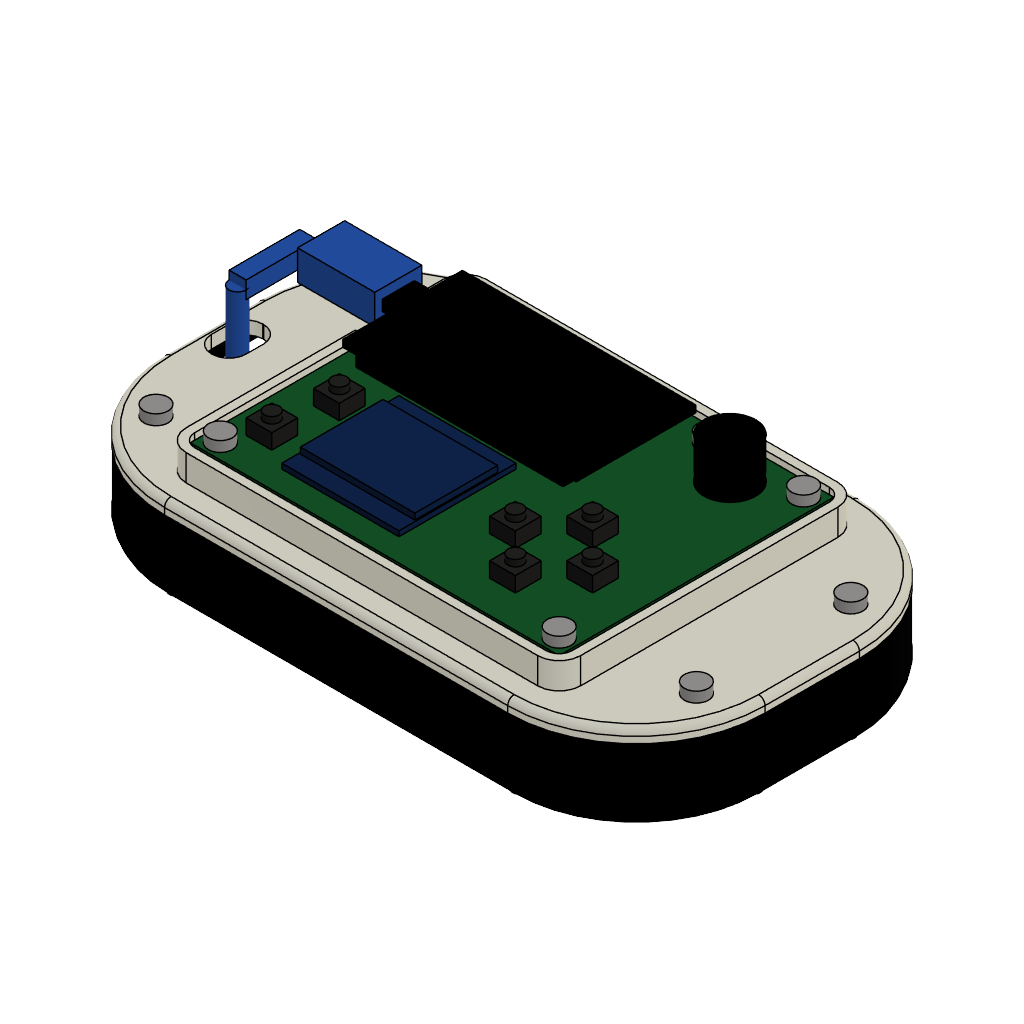
tiny_arcade_case (Autodesk Fusion 360 design; units mm, degrees)
Autodesk Fusion 360 part; units mm, degrees
ref_plane "WorkPlane1" through (0, 0, 2.4) normal (0, 0, 1) x (1, 0, 0) in component "Power bank"
sketch "Sketch1" plane through (0, 0, 2.4) normal (0, 0, 1) x (1, 0, 0) in component "Power bank"
  line L0 (-45, -35) -> (55, -35)
  line L1 (55, -35) -> (55, 35)
  line L2 (55, 35) -> (-45, 35)
  line L3 (-45, 35) -> (-45, -35)
extrude "Extrude1" add sketch "Sketch1" along normal blind 15 makes body 1 in component "Power bank"
fillet "Fillet1" radius 4 4 edges at (-45, 35, 9.9) (55, 35, 9.9) (55, -35, 9.9) (-45, -35, 9.9) on bodies 1 in component "Power bank"
fillet "Fillet2" radius 2 128 edges at (-43.8284, -33.8284, 17.4) (-45, 0, 17.4) (-43.8284, 33.8284, 17.4) (5, 35, 17.4) (53.8284, 33.8284, 17.4) (55, 0, 17.4) (53.8284, -33.8284, 17.4) (5, -35, 17.4) (-43.8284, -33.8284, 2.4) (5, -35, 2.4) (53.8284, -33.8284, 2.4) (55, 0, 2.4) (53.8284, 33.8284, 2.4) (5, 35, 2.4) (-43.8284, 33.8284, 2.4) (-45, 0, 2.4) (-45, 0, 17.4) (-43.8284, -33.8284, 17.4) (5, -35, 17.4) (53.8284, -33.8284, 17.4) (55, 0, 17.4) (53.8284, 33.8284, 17.4) (5, 35, 17.4) (-43.8284, 33.8284, 17.4) (-45, 0, 2.4) (-43.8284, -33.8284, 2.4) (5, -35, 2.4) (53.8284, -33.8284, 2.4) (55, 0, 2.4) (53.8284, 33.8284, 2.4) (5, 35, 2.4) (-43.8284, 33.8284, 2.4) (5, -35, 17.4) (53.8284, -33.8284, 17.4) (55, 0, 17.4) (53.8284, 33.8284, 17.4) (5, 35, 17.4) (-43.8284, 33.8284, 17.4) (-45, 0, 17.4) (-43.8284, -33.8284, 17.4) (53.8284, -33.8284, 17.4) (5, -35, 17.4) (-43.8284, -33.8284, 17.4) (-45, 0, 17.4) (-43.8284, 33.8284, 17.4) (5, 35, 17.4) (53.8284, 33.8284, 17.4) (55, 0, 17.4) (55, 0, 17.4) (53.8284, 33.8284, 17.4) (5, 35, 17.4) (-43.8284, 33.8284, 17.4) (-45, 0, 17.4) (-43.8284, -33.8284, 17.4) (5, -35, 17.4) (53.8284, -33.8284, 17.4) (53.8284, 33.8284, 17.4) (55, 0, 17.4) (53.8284, -33.8284, 17.4) (5, -35, 17.4) (-43.8284, -33.8284, 17.4) (-45, 0, 17.4) (-43.8284, 33.8284, 17.4) (5, 35, 17.4) (5, 35, 17.4) (-43.8284, 33.8284, 17.4) (-45, 0, 17.4) (-43.8284, -33.8284, 17.4) (5, -35, 17.4) (53.8284, -33.8284, 17.4) (55, 0, 17.4) (53.8284, 33.8284, 17.4) (-43.8284, 33.8284, 17.4) (5, 35, 17.4) (53.8284, 33.8284, 17.4) (55, 0, 17.4) (53.8284, -33.8284, 17.4) (5, -35, 17.4) (-43.8284, -33.8284, 17.4) (-45, 0, 17.4) (53.8284, -33.8284, 2.4) (55, 0, 2.4) (53.8284, 33.8284, 2.4) (5, 35, 2.4) (-43.8284, 33.8284, 2.4) (-45, 0, 2.4) (-43.8284, -33.8284, 2.4) (5, -35, 2.4) (55, 0, 2.4) (53.8284, 33.8284, 2.4) (5, 35, 2.4) (-43.8284, 33.8284, 2.4) (-45, 0, 2.4) (-43.8284, -33.8284, 2.4) (5, -35, 2.4) (53.8284, -33.8284, 2.4) (53.8284, 33.8284, 2.4) (5, 35, 2.4) (-43.8284, 33.8284, 2.4) (-45, 0, 2.4) (-43.8284, -33.8284, 2.4) (5, -35, 2.4) (53.8284, -33.8284, 2.4) (55, 0, 2.4) (-43.8284, 33.8284, 2.4) (-45, 0, 2.4) (-43.8284, -33.8284, 2.4) (5, -35, 2.4) (53.8284, -33.8284, 2.4) (55, 0, 2.4) (53.8284, 33.8284, 2.4) (5, 35, 2.4) (5, 35, 2.4) (-43.8284, 33.8284, 2.4) (-45, 0, 2.4) (-43.8284, -33.8284, 2.4) (5, -35, 2.4) (53.8284, -33.8284, 2.4) (55, 0, 2.4) (53.8284, 33.8284, 2.4) (5, -35, 2.4) (53.8284, -33.8284, 2.4) (55, 0, 2.4) (53.8284, 33.8284, 2.4) (5, 35, 2.4) (-43.8284, 33.8284, 2.4) (-45, 0, 2.4) (-43.8284, -33.8284, 2.4) on bodies 1 in component "Power bank"
ref_plane "WorkPlane1" through (0, 0, 24.9) normal (0, 0, 1) x (1, 0, 0) in component "Board"
sketch "Sketch1 (2)" plane through (0, 0, 24.9) normal (0, 0, 1) x (1, 0, 0) in component "Board"
  line L0 (-43, -32) -> (43, -32)
  line L1 (43, -32) -> (43, 32)
  line L2 (43, 32) -> (-43, 32)
  line L3 (-43, 32) -> (-43, -32)
extrude "Extrude1'" add sketch "Sketch1 (2)" along normal blind 1.6 separate body makes body 2 in component "Board"
ref_plane "WorkPlane2" through (0, 0, 23.9) normal (0, 0, 1) x (1, 0, 0) in component "Board"
sketch "Sketch2" plane through (0, 0, 23.9) normal (0, 0, 1) x (1, 0, 0) in component "Board"
  circle A0 centre (-39.5, -28.5) radius 1.6
extrude "Extrude2" add sketch "Sketch2" along normal blind 3.6 separate body makes body 3 in component "Board"
ref_plane "WorkPlane3" through (0, 0, 23.9) normal (0, 0, 1) x (1, 0, 0) in component "Board"
sketch "Sketch3" plane through (0, 0, 23.9) normal (0, 0, 1) x (1, 0, 0) in component "Board"
  circle A0 centre (39.5, -28.5) radius 1.6
extrude "Extrude3" add sketch "Sketch3" along normal blind 3.6 separate body makes body 4 in component "Board"
ref_plane "WorkPlane4" through (0, 0, 23.9) normal (0, 0, 1) x (1, 0, 0) in component "Board"
sketch "Sketch4" plane through (0, 0, 23.9) normal (0, 0, 1) x (1, 0, 0) in component "Board"
  circle A0 centre (39.5, 28.5) radius 1.6
extrude "Extrude4" add sketch "Sketch4" along normal blind 3.6 separate body makes body 5 in component "Board"
ref_plane "WorkPlane5" through (0, 0, 23.9) normal (0, 0, 1) x (1, 0, 0) in component "Board"
sketch "Sketch5" plane through (0, 0, 23.9) normal (0, 0, 1) x (1, 0, 0) in component "Board"
  circle A0 centre (17.5, 28.5) radius 1.6
extrude "Extrude5" add sketch "Sketch5" along normal blind 3.6 separate body makes body 6 in component "Board"
combine "Combine1" operation cut target body 2 tool bodies 3 4 5 6 in component "Board"
ref_plane "WorkPlane6" through (0, 0, 26.5) normal (0, 0, 1) x (1, 0, 0) in component "Board"
sketch "Sketch6" plane through (0, 0, 26.5) normal (0, 0, 1) x (1, 0, 0) in component "Board"
  line L0 (-38.95, 27.95) -> (9.35, 27.95)
  line L1 (9.35, 27.95) -> (9.35, 30.45)
  line L2 (9.35, 30.45) -> (-38.95, 30.45)
  line L3 (-38.95, 30.45) -> (-38.95, 27.95)
extrude "Extrude6" add sketch "Sketch6" along normal blind 2.5 separate body makes body 7 in component "Board"
ref_plane "WorkPlane7" through (0, 0, 26.5) normal (0, 0, 1) x (1, 0, 0) in component "Board"
sketch "Sketch7" plane through (0, 0, 26.5) normal (0, 0, 1) x (1, 0, 0) in component "Board"
  line L0 (-38.95, 2.55) -> (9.35, 2.55)
  line L1 (9.35, 2.55) -> (9.35, 5.05)
  line L2 (9.35, 5.05) -> (-38.95, 5.05)
  line L3 (-38.95, 5.05) -> (-38.95, 2.55)
extrude "Extrude7" add sketch "Sketch7" along normal blind 2.5 separate body makes body 8 in component "Board"
ref_plane "WorkPlane8" through (0, 0, 29) normal (0, 0, 1) x (1, 0, 0) in component "Board"
sketch "Sketch8" plane through (0, 0, 29) normal (0, 0, 1) x (1, 0, 0) in component "Board"
  line L0 (-42, 2.55) -> (12.4, 2.55)
  line L1 (12.4, 2.55) -> (12.4, 30.45)
  line L2 (12.4, 30.45) -> (-42, 30.45)
  line L3 (-42, 30.45) -> (-42, 2.55)
extrude "Extrude8" add sketch "Sketch8" along normal blind 1.6 separate body makes body 9 in component "Board"
ref_plane "WorkPlane9" through (0, 0, 30.6) normal (0, 0, 1) x (1, 0, 0) in component "Board"
sketch "Sketch9" plane through (0, 0, 30.6) normal (0, 0, 1) x (1, 0, 0) in component "Board"
  line L0 (-13.1, 7.5) -> (12.4, 7.5)
  line L1 (12.4, 7.5) -> (12.4, 25.5)
  line L2 (12.4, 25.5) -> (-13.1, 25.5)
  line L3 (-13.1, 25.5) -> (-13.1, 7.5)
extrude "Extrude9" add sketch "Sketch9" along normal blind 3.1 separate body makes body 10 in component "Board"
ref_plane "WorkPlane10" through (0, 0, 30.6) normal (0, 0, 1) x (1, 0, 0) in component "Board"
sketch "Sketch10" plane through (0, 0, 30.6) normal (0, 0, 1) x (1, 0, 0) in component "Board"
  line L0 (-43, 12.75) -> (-37.5, 12.75)
  line L1 (-37.5, 12.75) -> (-37.5, 20.25)
  line L2 (-37.5, 20.25) -> (-43, 20.25)
  line L3 (-43, 20.25) -> (-43, 12.75)
extrude "Extrude10" add sketch "Sketch10" along normal blind 2.5 separate body makes body 11 in component "Board"
ref_plane "WorkPlane11" through (0, 0, 26.5) normal (0, 0, 1) x (1, 0, 0) in component "Board"
sketch "Sketch11" plane through (0, 0, 26.5) normal (0, 0, 1) x (1, 0, 0) in component "Board"
  line L0 (-15.92, -4.52) -> (-5.76, -4.52)
  line L1 (-5.76, -4.52) -> (-5.76, -2.02)
  line L2 (-5.76, -2.02) -> (-15.92, -2.02)
  line L3 (-15.92, -2.02) -> (-15.92, -4.52)
extrude "Extrude11" add sketch "Sketch11" along normal blind 2.5 separate body makes body 12 in component "Board"
ref_plane "WorkPlane12" through (0, 0, 29) normal (0, 0, 1) x (1, 0, 0) in component "Board"
sketch "Sketch12" plane through (0, 0, 29) normal (0, 0, 1) x (1, 0, 0) in component "Board"
  line L0 (-24.49, -29.17) -> (2.81, -29.17)
  line L1 (2.81, -29.17) -> (2.81, -1.87)
  line L2 (2.81, -1.87) -> (-24.49, -1.87)
  line L3 (-24.49, -1.87) -> (-24.49, -29.17)
extrude "Extrude12" add sketch "Sketch12" along normal blind 1.2 separate body makes body 13 in component "Board"
ref_plane "WorkPlane13" through (0, 0, 30.2) normal (0, 0, 1) x (1, 0, 0) in component "Board"
sketch "Sketch13" plane through (0, 0, 30.2) normal (0, 0, 1) x (1, 0, 0) in component "Board"
  line L0 (-24.19, -25.15) -> (2.51, -25.15)
  line L1 (2.51, -25.15) -> (2.51, -5.89)
  line L2 (2.51, -5.89) -> (-24.19, -5.89)
  line L3 (-24.19, -5.89) -> (-24.19, -25.15)
extrude "Extrude13" add sketch "Sketch13" along normal blind 1.4 separate body makes body 14 in component "Board"
ref_plane "WorkPlane14" through (0, 0, 26.5) normal (0, 0, 1) x (1, 0, 0) in component "Board"
sketch "Sketch14" plane through (0, 0, 26.5) normal (0, 0, 1) x (1, 0, 0) in component "Board"
  circle A0 centre (27.73, 23.08) radius 6
extrude "Extrude14" add sketch "Sketch14" along normal blind 9.5 separate body makes body 15 in component "Board"
ref_plane "WorkPlane15" through (0, 0, 26.5) normal (0, 0, 1) x (1, 0, 0) in component "Board"
sketch "Sketch15" plane through (0, 0, 26.5) normal (0, 0, 1) x (1, 0, 0) in component "Board"
  line L0 (-36.08, -10.19) -> (-30.08, -10.19)
  line L1 (-30.08, -10.19) -> (-30.08, -4.19)
  line L2 (-30.08, -4.19) -> (-36.08, -4.19)
  line L3 (-36.08, -4.19) -> (-36.08, -10.19)
extrude "Extrude15" add sketch "Sketch15" along normal blind 3.5 separate body makes body 16 in component "Board"
ref_plane "WorkPlane16" through (0, 0, 30) normal (0, 0, 1) x (1, 0, 0) in component "Board"
sketch "Sketch16" plane through (0, 0, 30) normal (0, 0, 1) x (1, 0, 0) in component "Board"
  circle A0 centre (-33.08, -7.19) radius 1.75
extrude "Extrude16" add sketch "Sketch16" along normal blind 1.5 separate body makes body 17 in component "Board"
ref_plane "WorkPlane17" through (0, 0, 26.5) normal (0, 0, 1) x (1, 0, 0) in component "Board"
sketch "Sketch17" plane through (0, 0, 26.5) normal (0, 0, 1) x (1, 0, 0) in component "Board"
  line L0 (-38, -24) -> (-32, -24)
  line L1 (-32, -24) -> (-32, -18)
  line L2 (-32, -18) -> (-38, -18)
  line L3 (-38, -18) -> (-38, -24)
extrude "Extrude17" add sketch "Sketch17" along normal blind 3.5 separate body makes body 18 in component "Board"
ref_plane "WorkPlane18" through (0, 0, 30) normal (0, 0, 1) x (1, 0, 0) in component "Board"
sketch "Sketch18" plane through (0, 0, 30) normal (0, 0, 1) x (1, 0, 0) in component "Board"
  circle A0 centre (-35, -21) radius 1.75
extrude "Extrude18" add sketch "Sketch18" along normal blind 1.5 separate body makes body 19 in component "Board"
ref_plane "WorkPlane19" through (0, 0, 26.5) normal (0, 0, 1) x (1, 0, 0) in component "Board"
sketch "Sketch19" plane through (0, 0, 26.5) normal (0, 0, 1) x (1, 0, 0) in component "Board"
  line L0 (19.24, -6.46) -> (25.24, -6.46)
  line L1 (25.24, -6.46) -> (25.24, -0.46)
  line L2 (25.24, -0.46) -> (19.24, -0.46)
  line L3 (19.24, -0.46) -> (19.24, -6.46)
extrude "Extrude19" add sketch "Sketch19" along normal blind 3.5 separate body makes body 20 in component "Board"
ref_plane "WorkPlane20" through (0, 0, 30) normal (0, 0, 1) x (1, 0, 0) in component "Board"
sketch "Sketch20" plane through (0, 0, 30) normal (0, 0, 1) x (1, 0, 0) in component "Board"
  circle A0 centre (22.24, -3.46) radius 1.75
extrude "Extrude20" add sketch "Sketch20" along normal blind 1.5 separate body makes body 21 in component "Board"
ref_plane "WorkPlane21" through (0, 0, 26.5) normal (0, 0, 1) x (1, 0, 0) in component "Board"
sketch "Sketch21" plane through (0, 0, 26.5) normal (0, 0, 1) x (1, 0, 0) in component "Board"
  line L0 (19.24, -24.46) -> (25.24, -24.46)
  line L1 (25.24, -24.46) -> (25.24, -18.46)
  line L2 (25.24, -18.46) -> (19.24, -18.46)
  line L3 (19.24, -18.46) -> (19.24, -24.46)
extrude "Extrude21" add sketch "Sketch21" along normal blind 3.5 separate body makes body 22 in component "Board"
ref_plane "WorkPlane22" through (0, 0, 30) normal (0, 0, 1) x (1, 0, 0) in component "Board"
sketch "Sketch22" plane through (0, 0, 30) normal (0, 0, 1) x (1, 0, 0) in component "Board"
  circle A0 centre (22.24, -21.46) radius 1.75
extrude "Extrude22" add sketch "Sketch22" along normal blind 1.5 separate body makes body 23 in component "Board"
ref_plane "WorkPlane23" through (0, 0, 26.5) normal (0, 0, 1) x (1, 0, 0) in component "Board"
sketch "Sketch23" plane through (0, 0, 26.5) normal (0, 0, 1) x (1, 0, 0) in component "Board"
  line L0 (10.24, -15.46) -> (16.24, -15.46)
  line L1 (16.24, -15.46) -> (16.24, -9.46)
  line L2 (16.24, -9.46) -> (10.24, -9.46)
  line L3 (10.24, -9.46) -> (10.24, -15.46)
extrude "Extrude23" add sketch "Sketch23" along normal blind 3.5 separate body makes body 24 in component "Board"
ref_plane "WorkPlane24" through (0, 0, 30) normal (0, 0, 1) x (1, 0, 0) in component "Board"
sketch "Sketch24" plane through (0, 0, 30) normal (0, 0, 1) x (1, 0, 0) in component "Board"
  circle A0 centre (13.24, -12.46) radius 1.75
extrude "Extrude24" add sketch "Sketch24" along normal blind 1.5 separate body makes body 25 in component "Board"
ref_plane "WorkPlane25" through (0, 0, 26.5) normal (0, 0, 1) x (1, 0, 0) in component "Board"
sketch "Sketch25" plane through (0, 0, 26.5) normal (0, 0, 1) x (1, 0, 0) in component "Board"
  line L0 (28.24, -15.46) -> (34.24, -15.46)
  line L1 (34.24, -15.46) -> (34.24, -9.46)
  line L2 (34.24, -9.46) -> (28.24, -9.46)
  line L3 (28.24, -9.46) -> (28.24, -15.46)
extrude "Extrude25" add sketch "Sketch25" along normal blind 3.5 separate body makes body 26 in component "Board"
ref_plane "WorkPlane26" through (0, 0, 30) normal (0, 0, 1) x (1, 0, 0) in component "Board"
sketch "Sketch26" plane through (0, 0, 30) normal (0, 0, 1) x (1, 0, 0) in component "Board"
  circle A0 centre (31.24, -12.46) radius 1.75
extrude "Extrude26" add sketch "Sketch26" along normal blind 1.5 separate body makes body 27 in component "Board"
ref_plane "WorkPlane1" through (0, 0, 6.4) normal (0, 0, 1) x (1, 0, 0) in component "USB cable"
sketch "Sketch1 (3)" plane through (0, 0, 6.4) normal (0, 0, 1) x (1, 0, 0) in component "USB cable"
  line L0 (-63, -6) -> (-45.5, -6)
  line L1 (-45.5, -6) -> (-45.5, 6)
  line L2 (-45.5, 6) -> (-63, 6)
  line L3 (-63, 6) -> (-63, -6)
extrude "Extrude1''" add sketch "Sketch1 (3)" along normal blind 7 separate body makes body 28 in component "USB cable"
ref_plane "WorkPlane2" through (0, 0, 9.9) normal (0, 0, 1) x (1, 0, 0) in component "USB cable"
sketch "Sketch2 (2)" plane through (0, 0, 9.9) normal (0, 0, 1) x (1, 0, 0) in component "USB cable"
  circle A0 centre (-64, 0) radius 2
extrude "Extrude2'" add sketch "Sketch2 (2)" along normal blind 21.95 separate body makes body 29 in component "USB cable"
ref_plane "WorkPlane3" through (0, 0, 29.85) normal (0, 0, 1) x (1, 0, 0) in component "USB cable"
sketch "Sketch3 (2)" plane through (0, 0, 29.85) normal (0, 0, 1) x (1, 0, 0) in component "USB cable"
  line L0 (-66, 0) -> (-62, 0)
  line L1 (-62, 0) -> (-62, 16.5)
  line L2 (-62, 16.5) -> (-66, 16.5)
  line L3 (-66, 16.5) -> (-66, 0)
extrude "Extrude3'" add sketch "Sketch3 (2)" along normal blind 4 separate body makes body 30 in component "USB cable"
ref_plane "WorkPlane4" through (0, 0, 28.35) normal (0, 0, 1) x (1, 0, 0) in component "USB cable"
sketch "Sketch4 (2)" plane through (0, 0, 28.35) normal (0, 0, 1) x (1, 0, 0) in component "USB cable"
  line L0 (-61, 11) -> (-43, 11)
  line L1 (-43, 11) -> (-43, 22)
  line L2 (-43, 22) -> (-61, 22)
  line L3 (-61, 22) -> (-61, 11)
extrude "Extrude4'" add sketch "Sketch4 (2)" along normal blind 7 separate body makes body 31 in component "USB cable"
sketch "Sketch1 (4)" plane through (0, 0, 0) normal (0, 0, 1) x (1, 0, 0) in component "Body"
  line L0 (-70, -41) -> (70, -41)
  line L1 (70, -41) -> (70, 41)
  line L2 (70, 41) -> (-70, 41)
  line L3 (-70, 41) -> (-70, -41)
extrude "Extrude1'''" add sketch "Sketch1 (4)" along normal blind 17.9 separate body makes body 32 in component "Body"
fillet "Fillet1'" radius 30 4 edges at (-70, 41, 8.95) (70, 41, 8.95) (70, -41, 8.95) (-70, -41, 8.95) on bodies 32 in component "Body"
fillet "Fillet2'" radius 4 64 edges at (-61.2132, -32.2132, 0) (0, -41, 0) (61.2132, -32.2132, 0) (70, 0, 0) (61.2132, 32.2132, 0) (0, 41, 0) (-61.2132, 32.2132, 0) (-70, 0, 0) (-70, 0, 0) (-61.2132, -32.2132, 0) (0, -41, 0) (61.2132, -32.2132, 0) (70, 0, 0) (61.2132, 32.2132, 0) (0, 41, 0) (-61.2132, 32.2132, 0) (61.2132, -32.2132, 0) (70, 0, 0) (61.2132, 32.2132, 0) (0, 41, 0) (-61.2132, 32.2132, 0) (-70, 0, 0) (-61.2132, -32.2132, 0) (0, -41, 0) (70, 0, 0) (61.2132, 32.2132, 0) (0, 41, 0) (-61.2132, 32.2132, 0) (-70, 0, 0) (-61.2132, -32.2132, 0) (0, -41, 0) (61.2132, -32.2132, 0) (61.2132, 32.2132, 0) (0, 41, 0) (-61.2132, 32.2132, 0) (-70, 0, 0) (-61.2132, -32.2132, 0) (0, -41, 0) (61.2132, -32.2132, 0) (70, 0, 0) (-61.2132, 32.2132, 0) (-70, 0, 0) (-61.2132, -32.2132, 0) (0, -41, 0) (61.2132, -32.2132, 0) (70, 0, 0) (61.2132, 32.2132, 0) (0, 41, 0) (0, 41, 0) (-61.2132, 32.2132, 0) (-70, 0, 0) (-61.2132, -32.2132, 0) (0, -41, 0) (61.2132, -32.2132, 0) (70, 0, 0) (61.2132, 32.2132, 0) (0, -41, 0) (61.2132, -32.2132, 0) (70, 0, 0) (61.2132, 32.2132, 0) (0, 41, 0) (-61.2132, 32.2132, 0) (-70, 0, 0) (-61.2132, -32.2132, 0) on bodies 32 in component "Body"
shell "Shell1" thickness 2.4 removed faces 1 at (13.3333, -13.6667, 17.9) on bodies 32 in component "Body"
ref_plane "WorkPlane1" through (0, 0, 0.5) normal (0, 0, 1) x (1, 0, 0) in component "Body"
sketch "Sketch2 (3)" plane through (0, 0, 0.5) normal (0, 0, 1) x (1, 0, 0) in component "Body"
  circle A0 centre (61, 18) radius 3.5
extrude "Extrude2''" add sketch "Sketch2 (3)" along normal blind 17.4 separate body makes body 33 in component "Body"
ref_plane "WorkPlane2" through (0, 0, 0.5) normal (0, 0, 1) x (1, 0, 0) in component "Body"
sketch "Sketch3 (3)" plane through (0, 0, 0.5) normal (0, 0, 1) x (1, 0, 0) in component "Body"
  circle A0 centre (61, -18) radius 3.5
extrude "Extrude3''" add sketch "Sketch3 (3)" along normal blind 17.4 separate body makes body 34 in component "Body"
ref_plane "WorkPlane3" through (0, 0, 0.5) normal (0, 0, 1) x (1, 0, 0) in component "Body"
sketch "Sketch4 (3)" plane through (0, 0, 0.5) normal (0, 0, 1) x (1, 0, 0) in component "Body"
  circle A0 centre (-58, 25) radius 3.5
extrude "Extrude4''" add sketch "Sketch4 (3)" along normal blind 17.4 separate body makes body 35 in component "Body"
ref_plane "WorkPlane4" through (0, 0, 0.5) normal (0, 0, 1) x (1, 0, 0) in component "Body"
sketch "Sketch5 (2)" plane through (0, 0, 0.5) normal (0, 0, 1) x (1, 0, 0) in component "Body"
  circle A0 centre (-58, -25) radius 3.5
extrude "Extrude5'" add sketch "Sketch5 (2)" along normal blind 17.4 separate body makes body 36 in component "Body"
ref_plane "WorkPlane5" through (0, 0, 0.5) normal (0, 0, 1) x (1, 0, 0) in component "Body"
sketch "Sketch6 (2)" plane through (0, 0, 0.5) normal (0, 0, 1) x (1, 0, 0) in component "Body"
  line L0 (55.5, -30) -> (57.5, -30)
  line L1 (57.5, -30) -> (57.5, -20)
  line L2 (57.5, -20) -> (55.5, -20)
  line L3 (55.5, -20) -> (55.5, -30)
extrude "Extrude6'" add sketch "Sketch6 (2)" along normal blind 10.4 separate body makes body 37 in component "Body"
ref_plane "WorkPlane6" through (0, 0, 0.5) normal (0, 0, 1) x (1, 0, 0) in component "Body"
sketch "Sketch7 (2)" plane through (0, 0, 0.5) normal (0, 0, 1) x (1, 0, 0) in component "Body"
  line L0 (55.5, 20) -> (57.5, 20)
  line L1 (57.5, 20) -> (57.5, 30)
  line L2 (57.5, 30) -> (55.5, 30)
  line L3 (55.5, 30) -> (55.5, 20)
extrude "Extrude7'" add sketch "Sketch7 (2)" along normal blind 10.4 separate body makes body 38 in component "Body"
ref_plane "WorkPlane7" through (0, 0, 0.5) normal (0, 0, 1) x (1, 0, 0) in component "Body"
sketch "Sketch8 (2)" plane through (0, 0, 0.5) normal (0, 0, 1) x (1, 0, 0) in component "Body"
  line L0 (-47.5, -30) -> (-45.5, -30)
  line L1 (-45.5, -30) -> (-45.5, -20)
  line L2 (-45.5, -20) -> (-47.5, -20)
  line L3 (-47.5, -20) -> (-47.5, -30)
extrude "Extrude8'" add sketch "Sketch8 (2)" along normal blind 10.4 separate body makes body 39 in component "Body"
ref_plane "WorkPlane8" through (0, 0, 0.5) normal (0, 0, 1) x (1, 0, 0) in component "Body"
sketch "Sketch9 (2)" plane through (0, 0, 0.5) normal (0, 0, 1) x (1, 0, 0) in component "Body"
  line L0 (-47.5, 20) -> (-45.5, 20)
  line L1 (-45.5, 20) -> (-45.5, 30)
  line L2 (-45.5, 30) -> (-47.5, 30)
  line L3 (-47.5, 30) -> (-47.5, 20)
extrude "Extrude9'" add sketch "Sketch9 (2)" along normal blind 10.4 separate body makes body 40 in component "Body"
combine "Combine1'" operation add target body 32 tool bodies 33 34 35 36 37 38 39 40 in component "Body"
ref_plane "WorkPlane9" through (0, 0, 9.9) normal (0, 0, 1) x (1, 0, 0) in component "Body"
sketch "Sketch10 (2)" plane through (0, 0, 9.9) normal (0, 0, 1) x (1, 0, 0) in component "Body"
  circle A0 centre (61, 18) radius 1.25
extrude "Extrude10'" add sketch "Sketch10 (2)" along normal blind 9 separate body makes body 41 in component "Body"
ref_plane "WorkPlane10" through (0, 0, 9.9) normal (0, 0, 1) x (1, 0, 0) in component "Body"
sketch "Sketch11 (2)" plane through (0, 0, 9.9) normal (0, 0, 1) x (1, 0, 0) in component "Body"
  circle A0 centre (61, -18) radius 1.25
extrude "Extrude11'" add sketch "Sketch11 (2)" along normal blind 9 separate body makes body 42 in component "Body"
ref_plane "WorkPlane11" through (0, 0, 9.9) normal (0, 0, 1) x (1, 0, 0) in component "Body"
sketch "Sketch12 (2)" plane through (0, 0, 9.9) normal (0, 0, 1) x (1, 0, 0) in component "Body"
  circle A0 centre (-58, 25) radius 1.25
extrude "Extrude12'" add sketch "Sketch12 (2)" along normal blind 9 separate body makes body 43 in component "Body"
ref_plane "WorkPlane12" through (0, 0, 9.9) normal (0, 0, 1) x (1, 0, 0) in component "Body"
sketch "Sketch13 (2)" plane through (0, 0, 9.9) normal (0, 0, 1) x (1, 0, 0) in component "Body"
  circle A0 centre (-58, -25) radius 1.25
extrude "Extrude13'" add sketch "Sketch13 (2)" along normal blind 9 separate body makes body 44 in component "Body"
combine "Combine2" operation cut target body 32 tool bodies 41 42 43 44 in component "Body"
ref_plane "WorkPlane13" through (0, 0, 4.4) normal (0, 0, 1) x (1, 0, 0) in component "Body"
sketch "Sketch14 (2)" plane through (0, 0, 4.4) normal (0, 0, 1) x (1, 0, 0) in component "Body"
  line L0 (-71, -20) -> (-44.5, -20)
  line L1 (-44.5, -20) -> (-44.5, 20)
  line L2 (-44.5, 20) -> (-71, 20)
  line L3 (-71, 20) -> (-71, -20)
extrude "Extrude14'" add sketch "Sketch14 (2)" along normal blind 11 separate body makes body 45 in component "Body"
combine "Combine3" operation cut target body 32 tool bodies 45 in component "Body"
ref_plane "WorkPlane1" through (0, 0, 17.9) normal (0, 0, 1) x (1, 0, 0) in component "Deck"
sketch "Sketch1 (5)" plane through (0, 0, 17.9) normal (0, 0, 1) x (1, 0, 0) in component "Deck"
  line L0 (-70, -41) -> (70, -41)
  line L1 (70, -41) -> (70, 41)
  line L2 (70, 41) -> (-70, 41)
  line L3 (-70, 41) -> (-70, -41)
extrude "Extrude1''''" add sketch "Sketch1 (5)" along normal blind 3 separate body makes body 46 in component "Deck"
fillet "Fillet1''" radius 30 4 edges at (-70, 41, 19.4) (70, 41, 19.4) (70, -41, 19.4) (-70, -41, 19.4) on bodies 46 in component "Deck"
fillet "Fillet2''" radius 1.5 64 edges at (-61.2132, -32.2132, 20.9) (-70, 0, 20.9) (-61.2132, 32.2132, 20.9) (0, 41, 20.9) (61.2132, 32.2132, 20.9) (70, 0, 20.9) (61.2132, -32.2132, 20.9) (0, -41, 20.9) (-70, 0, 20.9) (-61.2132, -32.2132, 20.9) (0, -41, 20.9) (61.2132, -32.2132, 20.9) (70, 0, 20.9) (61.2132, 32.2132, 20.9) (0, 41, 20.9) (-61.2132, 32.2132, 20.9) (0, -41, 20.9) (61.2132, -32.2132, 20.9) (70, 0, 20.9) (61.2132, 32.2132, 20.9) (0, 41, 20.9) (-61.2132, 32.2132, 20.9) (-70, 0, 20.9) (-61.2132, -32.2132, 20.9) (61.2132, -32.2132, 20.9) (0, -41, 20.9) (-61.2132, -32.2132, 20.9) (-70, 0, 20.9) (-61.2132, 32.2132, 20.9) (0, 41, 20.9) (61.2132, 32.2132, 20.9) (70, 0, 20.9) (70, 0, 20.9) (61.2132, 32.2132, 20.9) (0, 41, 20.9) (-61.2132, 32.2132, 20.9) (-70, 0, 20.9) (-61.2132, -32.2132, 20.9) (0, -41, 20.9) (61.2132, -32.2132, 20.9) (61.2132, 32.2132, 20.9) (70, 0, 20.9) (61.2132, -32.2132, 20.9) (0, -41, 20.9) (-61.2132, -32.2132, 20.9) (-70, 0, 20.9) (-61.2132, 32.2132, 20.9) (0, 41, 20.9) (0, 41, 20.9) (-61.2132, 32.2132, 20.9) (-70, 0, 20.9) (-61.2132, -32.2132, 20.9) (0, -41, 20.9) (61.2132, -32.2132, 20.9) (70, 0, 20.9) (61.2132, 32.2132, 20.9) (-61.2132, 32.2132, 20.9) (0, 41, 20.9) (61.2132, 32.2132, 20.9) (70, 0, 20.9) (61.2132, -32.2132, 20.9) (0, -41, 20.9) (-61.2132, -32.2132, 20.9) (-70, 0, 20.9) on bodies 46 in component "Deck"
ref_plane "WorkPlane2" through (0, 0, 20.89) normal (0, 0, 1) x (1, 0, 0) in component "Deck"
sketch "Sketch2 (4)" plane through (0, 0, 20.89) normal (0, 0, 1) x (1, 0, 0) in component "Deck"
  line L0 (-46, -35) -> (46, -35)
  line L1 (46, -35) -> (46, 35)
  line L2 (46, 35) -> (-46, 35)
  line L3 (-46, 35) -> (-46, -35)
extrude "Extrude2'''" add sketch "Sketch2 (4)" along normal blind 6.11 separate body makes body 47 in component "Deck"
fillet "Fillet3" radius 5 4 edges at (-46, 35, 23.945) (46, 35, 23.945) (46, -35, 23.945) (-46, -35, 23.945) on bodies 47 in component "Deck"
ref_plane "WorkPlane3" through (0, 0, 19.9) normal (0, 0, 1) x (1, 0, 0) in component "Deck"
sketch "Sketch3 (4)" plane through (0, 0, 19.9) normal (0, 0, 1) x (1, 0, 0) in component "Deck"
  line L0 (-44, -33) -> (44, -33)
  line L1 (44, -33) -> (44, 33)
  line L2 (44, 33) -> (-44, 33)
  line L3 (-44, 33) -> (-44, -33)
extrude "Extrude3'''" add sketch "Sketch3 (4)" along normal blind 8.1 separate body makes body 48 in component "Deck"
fillet "Fillet4" radius 3 4 edges at (-44, 33, 23.95) (44, 33, 23.95) (44, -33, 23.95) (-44, -33, 23.95) on bodies 48 in component "Deck"
ref_plane "WorkPlane4" through (0, 0, 21.4) normal (0, 0, 1) x (1, 0, 0) in component "Deck"
sketch "Sketch4 (4)" plane through (0, 0, 21.4) normal (0, 0, 1) x (1, 0, 0) in component "Deck"
  line L0 (-53, 9.5) -> (-42, 9.5)
  line L1 (-42, 9.5) -> (-42, 23.5)
  line L2 (-42, 23.5) -> (-53, 23.5)
  line L3 (-53, 23.5) -> (-53, 9.5)
extrude "Extrude4'''" add sketch "Sketch4 (4)" along normal blind 7.1 separate body makes body 49 in component "Deck"
combine "Combine1''" operation cut target body 47 tool bodies 48 49 in component "Deck"
ref_plane "WorkPlane5" through (0, 0, 20.89) normal (0, 0, 1) x (1, 0, 0) in component "Deck"
sketch "Sketch5 (3)" plane through (0, 0, 20.89) normal (0, 0, 1) x (1, 0, 0) in component "Deck"
  circle A0 centre (-39.5, -28.5) radius 3
extrude "Extrude5''" add sketch "Sketch5 (3)" along normal blind 4.01 separate body makes body 50 in component "Deck"
ref_plane "WorkPlane6" through (0, 0, 20.89) normal (0, 0, 1) x (1, 0, 0) in component "Deck"
sketch "Sketch6 (3)" plane through (0, 0, 20.89) normal (0, 0, 1) x (1, 0, 0) in component "Deck"
  circle A0 centre (39.5, -28.5) radius 3
extrude "Extrude6''" add sketch "Sketch6 (3)" along normal blind 4.01 separate body makes body 51 in component "Deck"
ref_plane "WorkPlane7" through (0, 0, 20.89) normal (0, 0, 1) x (1, 0, 0) in component "Deck"
sketch "Sketch7 (3)" plane through (0, 0, 20.89) normal (0, 0, 1) x (1, 0, 0) in component "Deck"
  circle A0 centre (39.5, 28.5) radius 3
extrude "Extrude7''" add sketch "Sketch7 (3)" along normal blind 4.01 separate body makes body 52 in component "Deck"
ref_plane "WorkPlane8" through (0, 0, 20.89) normal (0, 0, 1) x (1, 0, 0) in component "Deck"
sketch "Sketch8 (3)" plane through (0, 0, 20.89) normal (0, 0, 1) x (1, 0, 0) in component "Deck"
  circle A0 centre (17.5, 28.5) radius 3
extrude "Extrude8''" add sketch "Sketch8 (3)" along normal blind 4.01 separate body makes body 53 in component "Deck"
combine "Combine2'" operation add target body 46 tool bodies 47 50 51 52 53 in component "Deck"
ref_plane "WorkPlane9" through (0, 0, 16.9) normal (0, 0, 1) x (1, 0, 0) in component "Deck"
sketch "Sketch9 (3)" plane through (0, 0, 16.9) normal (0, 0, 1) x (1, 0, 0) in component "Deck"
  circle A0 centre (-39.5, -28.5) radius 1.25
extrude "Extrude9''" add sketch "Sketch9 (3)" along normal blind 9 separate body makes body 54 in component "Deck"
ref_plane "WorkPlane10" through (0, 0, 16.9) normal (0, 0, 1) x (1, 0, 0) in component "Deck"
sketch "Sketch10 (3)" plane through (0, 0, 16.9) normal (0, 0, 1) x (1, 0, 0) in component "Deck"
  circle A0 centre (39.5, -28.5) radius 1.25
extrude "Extrude10''" add sketch "Sketch10 (3)" along normal blind 9 separate body makes body 55 in component "Deck"
ref_plane "WorkPlane11" through (0, 0, 16.9) normal (0, 0, 1) x (1, 0, 0) in component "Deck"
sketch "Sketch11 (3)" plane through (0, 0, 16.9) normal (0, 0, 1) x (1, 0, 0) in component "Deck"
  circle A0 centre (39.5, 28.5) radius 1.25
extrude "Extrude11''" add sketch "Sketch11 (3)" along normal blind 9 separate body makes body 56 in component "Deck"
ref_plane "WorkPlane12" through (0, 0, 16.9) normal (0, 0, 1) x (1, 0, 0) in component "Deck"
sketch "Sketch12 (3)" plane through (0, 0, 16.9) normal (0, 0, 1) x (1, 0, 0) in component "Deck"
  circle A0 centre (17.5, 28.5) radius 1.25
extrude "Extrude12''" add sketch "Sketch12 (3)" along normal blind 9 separate body makes body 57 in component "Deck"
combine "Combine3'" operation cut target body 46 tool bodies 54 55 56 57 in component "Deck"
ref_plane "WorkPlane13" through (0, 0, 16.9) normal (0, 0, 1) x (1, 0, 0) in component "Deck"
sketch "Sketch13 (3)" plane through (0, 0, 16.9) normal (0, 0, 1) x (1, 0, 0) in component "Deck"
  circle A0 centre (61, 18) radius 1.7
extrude "Extrude13''" add sketch "Sketch13 (3)" along normal blind 5 separate body makes body 58 in component "Deck"
ref_plane "WorkPlane14" through (0, 0, 16.9) normal (0, 0, 1) x (1, 0, 0) in component "Deck"
sketch "Sketch14 (3)" plane through (0, 0, 16.9) normal (0, 0, 1) x (1, 0, 0) in component "Deck"
  circle A0 centre (61, -18) radius 1.7
extrude "Extrude14''" add sketch "Sketch14 (3)" along normal blind 5 separate body makes body 59 in component "Deck"
ref_plane "WorkPlane15" through (0, 0, 16.9) normal (0, 0, 1) x (1, 0, 0) in component "Deck"
sketch "Sketch15 (2)" plane through (0, 0, 16.9) normal (0, 0, 1) x (1, 0, 0) in component "Deck"
  circle A0 centre (-58, 25) radius 1.7
extrude "Extrude15'" add sketch "Sketch15 (2)" along normal blind 5 separate body makes body 60 in component "Deck"
ref_plane "WorkPlane16" through (0, 0, 16.9) normal (0, 0, 1) x (1, 0, 0) in component "Deck"
sketch "Sketch16 (2)" plane through (0, 0, 16.9) normal (0, 0, 1) x (1, 0, 0) in component "Deck"
  circle A0 centre (-58, -25) radius 1.7
extrude "Extrude16'" add sketch "Sketch16 (2)" along normal blind 5 separate body makes body 61 in component "Deck"
combine "Combine4" operation cut target body 46 tool bodies 58 59 60 61 in component "Deck"
ref_plane "WorkPlane17" through (0, 0, 16.9) normal (0, 0, 1) x (1, 0, 0) in component "Deck"
sketch "Sketch17 (2)" plane through (0, 0, 16.9) normal (0, 0, 1) x (1, 0, 0) in component "Deck"
  line L0 (-68, -6) -> (-60, -6)
  line L1 (-60, -6) -> (-60, 6)
  line L2 (-60, 6) -> (-68, 6)
  line L3 (-68, 6) -> (-68, -6)
extrude "Extrude17'" add sketch "Sketch17 (2)" along normal blind 5 separate body makes body 62 in component "Deck"
fillet "Fillet5" radius 3.9 4 edges at (-68, 6, 19.4) (-60, 6, 19.4) (-60, -6, 19.4) (-68, -6, 19.4) on bodies 62 in component "Deck"
combine "Combine5" operation cut target body 46 tool bodies 62 in component "Deck"
ref_plane "WorkPlane1" through (0, 0, 26.5) normal (0, 0, 1) x (1, 0, 0) in component "Board screws M3x8"
sketch "Sketch1 (6)" plane through (0, 0, 26.5) normal (0, 0, 1) x (1, 0, 0) in component "Board screws M3x8"
  circle A0 centre (-39.5, -28.5) radius 2.8
extrude "Extrude1'''''" add sketch "Sketch1 (6)" along normal blind 2.4 separate body makes body 63 in component "Board screws M3x8"
ref_plane "WorkPlane2" through (0, 0, 18.5) normal (0, 0, 1) x (1, 0, 0) in component "Board screws M3x8"
sketch "Sketch2 (5)" plane through (0, 0, 18.5) normal (0, 0, 1) x (1, 0, 0) in component "Board screws M3x8"
  circle A0 centre (-39.5, -28.5) radius 1.5
extrude "Extrude2''''" add sketch "Sketch2 (5)" along normal blind 8 separate body makes body 64 in component "Board screws M3x8"
ref_plane "WorkPlane3" through (0, 0, 26.5) normal (0, 0, 1) x (1, 0, 0) in component "Board screws M3x8"
sketch "Sketch3 (5)" plane through (0, 0, 26.5) normal (0, 0, 1) x (1, 0, 0) in component "Board screws M3x8"
  circle A0 centre (39.5, -28.5) radius 2.8
extrude "Extrude3''''" add sketch "Sketch3 (5)" along normal blind 2.4 separate body makes body 65 in component "Board screws M3x8"
ref_plane "WorkPlane4" through (0, 0, 18.5) normal (0, 0, 1) x (1, 0, 0) in component "Board screws M3x8"
sketch "Sketch4 (5)" plane through (0, 0, 18.5) normal (0, 0, 1) x (1, 0, 0) in component "Board screws M3x8"
  circle A0 centre (39.5, -28.5) radius 1.5
extrude "Extrude4''''" add sketch "Sketch4 (5)" along normal blind 8 separate body makes body 66 in component "Board screws M3x8"
ref_plane "WorkPlane5" through (0, 0, 26.5) normal (0, 0, 1) x (1, 0, 0) in component "Board screws M3x8"
sketch "Sketch5 (4)" plane through (0, 0, 26.5) normal (0, 0, 1) x (1, 0, 0) in component "Board screws M3x8"
  circle A0 centre (39.5, 28.5) radius 2.8
extrude "Extrude5'''" add sketch "Sketch5 (4)" along normal blind 2.4 separate body makes body 67 in component "Board screws M3x8"
ref_plane "WorkPlane6" through (0, 0, 18.5) normal (0, 0, 1) x (1, 0, 0) in component "Board screws M3x8"
sketch "Sketch6 (4)" plane through (0, 0, 18.5) normal (0, 0, 1) x (1, 0, 0) in component "Board screws M3x8"
  circle A0 centre (39.5, 28.5) radius 1.5
extrude "Extrude6'''" add sketch "Sketch6 (4)" along normal blind 8 separate body makes body 68 in component "Board screws M3x8"
ref_plane "WorkPlane7" through (0, 0, 26.5) normal (0, 0, 1) x (1, 0, 0) in component "Board screws M3x8"
sketch "Sketch7 (4)" plane through (0, 0, 26.5) normal (0, 0, 1) x (1, 0, 0) in component "Board screws M3x8"
  circle A0 centre (17.5, 28.5) radius 2.8
extrude "Extrude7'''" add sketch "Sketch7 (4)" along normal blind 2.4 separate body makes body 69 in component "Board screws M3x8"
ref_plane "WorkPlane8" through (0, 0, 18.5) normal (0, 0, 1) x (1, 0, 0) in component "Board screws M3x8"
sketch "Sketch8 (4)" plane through (0, 0, 18.5) normal (0, 0, 1) x (1, 0, 0) in component "Board screws M3x8"
  circle A0 centre (17.5, 28.5) radius 1.5
extrude "Extrude8'''" add sketch "Sketch8 (4)" along normal blind 8 separate body makes body 70 in component "Board screws M3x8"
ref_plane "WorkPlane1" through (0, 0, 20.9) normal (0, 0, 1) x (1, 0, 0) in component "Deck screws M3x10"
sketch "Sketch1 (7)" plane through (0, 0, 20.9) normal (0, 0, 1) x (1, 0, 0) in component "Deck screws M3x10"
  circle A0 centre (61, 18) radius 2.8
extrude "Extrude1''''''" add sketch "Sketch1 (7)" along normal blind 2.4 separate body makes body 71 in component "Deck screws M3x10"
ref_plane "WorkPlane2" through (0, 0, 10.9) normal (0, 0, 1) x (1, 0, 0) in component "Deck screws M3x10"
sketch "Sketch2 (6)" plane through (0, 0, 10.9) normal (0, 0, 1) x (1, 0, 0) in component "Deck screws M3x10"
  circle A0 centre (61, 18) radius 1.5
extrude "Extrude2'''''" add sketch "Sketch2 (6)" along normal blind 10 separate body makes body 72 in component "Deck screws M3x10"
ref_plane "WorkPlane3" through (0, 0, 20.9) normal (0, 0, 1) x (1, 0, 0) in component "Deck screws M3x10"
sketch "Sketch3 (6)" plane through (0, 0, 20.9) normal (0, 0, 1) x (1, 0, 0) in component "Deck screws M3x10"
  circle A0 centre (61, -18) radius 2.8
extrude "Extrude3'''''" add sketch "Sketch3 (6)" along normal blind 2.4 separate body makes body 73 in component "Deck screws M3x10"
ref_plane "WorkPlane4" through (0, 0, 10.9) normal (0, 0, 1) x (1, 0, 0) in component "Deck screws M3x10"
sketch "Sketch4 (6)" plane through (0, 0, 10.9) normal (0, 0, 1) x (1, 0, 0) in component "Deck screws M3x10"
  circle A0 centre (61, -18) radius 1.5
extrude "Extrude4'''''" add sketch "Sketch4 (6)" along normal blind 10 separate body makes body 74 in component "Deck screws M3x10"
ref_plane "WorkPlane5" through (0, 0, 20.9) normal (0, 0, 1) x (1, 0, 0) in component "Deck screws M3x10"
sketch "Sketch5 (5)" plane through (0, 0, 20.9) normal (0, 0, 1) x (1, 0, 0) in component "Deck screws M3x10"
  circle A0 centre (-58, 25) radius 2.8
extrude "Extrude5''''" add sketch "Sketch5 (5)" along normal blind 2.4 separate body makes body 75 in component "Deck screws M3x10"
ref_plane "WorkPlane6" through (0, 0, 10.9) normal (0, 0, 1) x (1, 0, 0) in component "Deck screws M3x10"
sketch "Sketch6 (5)" plane through (0, 0, 10.9) normal (0, 0, 1) x (1, 0, 0) in component "Deck screws M3x10"
  circle A0 centre (-58, 25) radius 1.5
extrude "Extrude6''''" add sketch "Sketch6 (5)" along normal blind 10 separate body makes body 76 in component "Deck screws M3x10"
ref_plane "WorkPlane7" through (0, 0, 20.9) normal (0, 0, 1) x (1, 0, 0) in component "Deck screws M3x10"
sketch "Sketch7 (5)" plane through (0, 0, 20.9) normal (0, 0, 1) x (1, 0, 0) in component "Deck screws M3x10"
  circle A0 centre (-58, -25) radius 2.8
extrude "Extrude7''''" add sketch "Sketch7 (5)" along normal blind 2.4 separate body makes body 77 in component "Deck screws M3x10"
ref_plane "WorkPlane8" through (0, 0, 10.9) normal (0, 0, 1) x (1, 0, 0) in component "Deck screws M3x10"
sketch "Sketch8 (5)" plane through (0, 0, 10.9) normal (0, 0, 1) x (1, 0, 0) in component "Deck screws M3x10"
  circle A0 centre (-58, -25) radius 1.5
extrude "Extrude8''''" add sketch "Sketch8 (5)" along normal blind 10 separate body makes body 78 in component "Deck screws M3x10"
combine "Combine1'''" operation add target body 63 tool bodies 64 in component "Board screws M3x8"
combine "Combine2''" operation add target body 65 tool bodies 66 in component "Board screws M3x8"
combine "Combine3''" operation add target body 67 tool bodies 68 in component "Board screws M3x8"
combine "Combine4'" operation add target body 69 tool bodies 70 in component "Board screws M3x8"
combine "Combine1''''" operation add target body 71 tool bodies 72 in component "Deck screws M3x10"
combine "Combine2'''" operation add target body 73 tool bodies 74 in component "Deck screws M3x10"
combine "Combine3'''" operation add target body 75 tool bodies 76 in component "Deck screws M3x10"
combine "Combine4''" operation add target body 77 tool bodies 78 in component "Deck screws M3x10"
component "Power bank" placed x (1, 0, 0) y (0, 1, 0) z (0, 0, 1) at (0, 0, 0)
component "Board" placed x (1, 0, 0) y (0, 1, 0) z (0, 0, 1) at (0, 0, 0)
component "USB cable" placed x (1, 0, 0) y (0, 1, 0) z (0, 0, 1) at (0, 0, 0)
component "Case" placed x (1, 0, 0) y (0, 1, 0) z (0, 0, 1) at (0, 0, 0)
component "Board screws M3x8" placed x (1, 0, 0) y (0, 1, 0) z (0, 0, 1) at (0, 0, 0)
component "Deck screws M3x10" placed x (1, 0, 0) y (0, 1, 0) z (0, 0, 1) at (0, 0, 0)
component "Body" placed x (1, 0, 0) y (0, 1, 0) z (0, 0, 1) at (0, 0, 0) in component "Case"
component "Deck" placed x (1, 0, 0) y (0, 1, 0) z (0, 0, 1) at (0, 0, 0) in component "Case"
named bodies: "power bank", "board", "U1", "U1 (1)", "U1 (2)", "U1 (3)", "U1 (4)", "DISP1", "DISP1 (1)", "DISP1 (2)", "BZ1", "SW1", "SW1 (1)", "SW2", "SW2 (1)", "SW3", "SW3 (1)", "SW4", "SW4 (1)", "SW5", "SW5 (1)", "SW6", "SW6 (1)", "cable", "cable (1)", "cable (2)", "cable (3)", "body", "deck", "board screw", "board screw (1)", "board screw (2)", "board screw (3)", "board screw (4)", "board screw (5)", "board screw (6)", "board screw (7)", "deck screw", "deck screw (1)", "deck screw (2)", "deck screw (3)", "deck screw (4)", "deck screw (5)", "deck screw (6)", "deck screw (7)"
